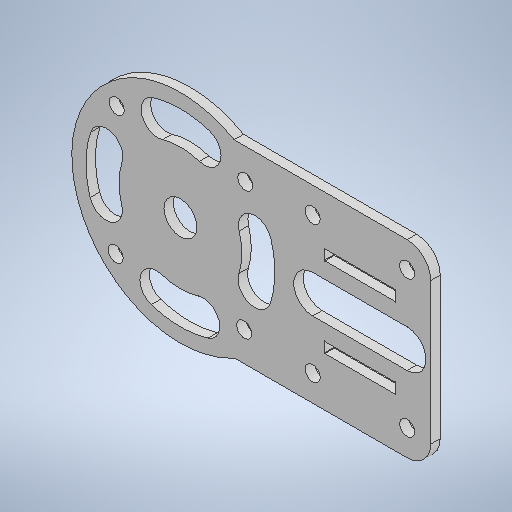
# Autodesk Inventor part: 3dp_pMount
Saved by Autodesk Inventor 2025.3 (Build 293356000, 356)
## iProperties
Created: 2026-10-04
Part Number: 3dp_pMount
Material: 一般
Document SubType Name: Modeling
Designer: yunto
Density: 1 g/cm^3
Appearance: 既定
Author: yunto
Autodesk Inventor part; units mm, degrees
ref_plane "YZ Plane" through (0, 0, 0) normal (1, 0, 0) x (0, 1, 0)
ref_plane "XZ Plane" through (0, 0, 0) normal (0, 1, 0) x (-1, 0, 0)
ref_plane "XY Plane" through (0, 0, 0) normal (0, 0, 1) x (1, 0, 0)
sketch "スケッチ1" plane through (0, 0, 0) normal (0, 0, 1) x (1, 0, 0)
  circle A0 centre (0, 0) radius 23
  circle A1 centre (0, 0) radius 3.5
  circle A2 centre (-13.4925, 13.7301) radius 1.6
  line L0 (-13.4925, 13.7301) -> (0, 0) construction
  circle A3 centre (-13.7301, -13.4925) radius 1.6
  circle A4 centre (13.4925, -13.7301) radius 1.6
  circle A5 centre (13.7301, 13.4925) radius 1.6
  line L1 (11.3578, 20) -> (53, 20)
  line L2 (53, 20) -> (53, -20)
  line L3 (53, -20) -> (11.3578, -20)
  line L4 (0, 23) -> (0, 0) construction
  line L5 (10.1768, -20.626) -> (11.4456, -20)
  arc A6 (-15.6924, 5.0988) -> (-15.779, -4.8241) centre (0, 0) ccw construction
  arc A7 (-19.0211, 6.1803) -> (-19.1261, -5.8474) centre (0, 0) ccw
  arc A8 (-12.3637, 4.0172) -> (-12.432, -3.8008) centre (0, 0) ccw
  arc A9 (-12.3637, 4.0172) -> (-19.0211, 6.1803) centre (-15.6924, 5.0988) ccw
  arc A10 (-19.1261, -5.8474) -> (-12.432, -3.8008) centre (-15.779, -4.8241) ccw
  arc A11 (-4.0172, -12.3637) -> (3.8008, -12.432) centre (0, 0) ccw
  arc A12 (-4.0172, -12.3637) -> (-6.1803, -19.0211) centre (-5.0988, -15.6924) ccw
  arc A13 (-6.1803, -19.0211) -> (5.8474, -19.1261) centre (0, 0) ccw
  arc A14 (5.8474, -19.1261) -> (3.8008, -12.432) centre (4.8241, -15.779) ccw
  arc A15 (12.3637, -4.0172) -> (12.432, 3.8008) centre (0, 0) ccw
  arc A16 (12.3637, -4.0172) -> (19.0211, -6.1803) centre (15.6924, -5.0988) ccw
  arc A17 (19.0211, -6.1803) -> (19.1261, 5.8474) centre (0, 0) ccw
  arc A18 (19.1261, 5.8474) -> (12.432, 3.8008) centre (15.779, 4.8241) ccw
  arc A19 (4.0172, 12.3637) -> (-3.8008, 12.432) centre (0, 0) ccw
  arc A20 (4.0172, 12.3637) -> (6.1803, 19.0211) centre (5.0988, 15.6924) ccw
  arc A21 (6.1803, 19.0211) -> (-5.8474, 19.1261) centre (0, 0) ccw
  arc A22 (-5.8474, 19.1261) -> (-3.8008, 12.432) centre (-4.8241, 15.779) ccw
  line L6 (-13.4925, 13.7301) -> (0, 0) construction
  line L7 (-16.4994, 0.144) -> (0, 0) construction
  line L8 (-15.779, -4.8241) -> (0, 0) construction
  line L9 (-15.6924, 5.0988) -> (0, 0) construction
  line L10 (48, -14.5) -> (28, -14.5) construction
  line L11 (28, -14.5) -> (28, 14.5) construction
  line L12 (28, 14.5) -> (48, 14.5) construction
  line L13 (48, 14.5) -> (48, -14.5) construction
  line L14 (48, -14.5) -> (28, 14.5) construction
  line L15 (28, -14.5) -> (48, 14.5) construction
  circle A23 centre (28, 14.5) radius 1.6
  circle A24 centre (48, 14.5) radius 1.6
  circle A25 centre (48, -14.5) radius 1.6
  circle A26 centre (28, -14.5) radius 1.6
  line L16 (0, 0) -> (38, 0) construction
  line L17 (45.5, -7.4) -> (30.5, -7.4)
  line L18 (30.5, -7.4) -> (30.5, -9.6)
  line L19 (30.5, -9.6) -> (45.5, -9.6)
  line L20 (45.5, -9.6) -> (45.5, -7.4)
  line L21 (45.5, -7.4) -> (30.5, -9.6) construction
  line L22 (30.5, -7.4) -> (45.5, -9.6) construction
  line L23 (38, 0) -> (38, -8.5) construction
  line L24 (45.5, 7.4) -> (30.5, 7.4)
  line L25 (30.5, 7.4) -> (30.5, 9.6)
  line L26 (30.5, 9.6) -> (45.5, 9.6)
  line L27 (45.5, 9.6) -> (45.5, 7.4)
  line L28 (45.5, 7.4) -> (30.5, 9.6) construction
  line L29 (30.5, 7.4) -> (45.5, 9.6) construction
  circle A27 centre (48, 0) radius 4
  circle A28 centre (28, 0) radius 4
  circle A29 centre (30.5, 9.6) radius 0.1
  circle A30 centre (30.5, 7.4) radius 0.1
  circle A31 centre (45.5, 9.6) radius 0.1
  circle A32 centre (45.5, 7.4) radius 0.1
  circle A33 centre (45.5, -7.4) radius 0.1
  circle A34 centre (30.5, -7.4) radius 0.1
  circle A35 centre (30.5, -9.6) radius 0.1
  circle A36 centre (45.5, -9.6) radius 0.1
  line L30 (28, 4) -> (48, 4)
  line L31 (48, -4) -> (28, -4)
  point P0 (38, 8.5)
  point P1 (45.4, -9.6)
  point P2 (30.6, -9.6)
  point P3 (30.5, -9.5)
  point P4 (30.5, -7.5)
  point P5 (30.6, -7.4)
  point P6 (45.4, -7.4)
  point P7 (45.5, -7.5)
  point P8 (45.5, -9.5)
  point P9 (45.4, 7.4)
  point P10 (30.6, 7.4)
  point P11 (30.5, 7.5)
  point P12 (30.5, 9.5)
  point P13 (30.6, 9.6)
  point P14 (45.4, 9.6)
  point P15 (45.5, 9.5)
  point P16 (45.5, 7.5)
  dimension "d0" = 7
  dimension "d1" = 46
  dimension "d2" = 19.25
  dimension "d3" = 3.2
  dimension "d6" = 360
  dimension "d19" = 44.5
  dimension "d31" = 360
  dimension "d33" = 45
  dimension "d35" = 13
  dimension "d36" = 20
  dimension "d37" = 35
  dimension "d38" = 3.2
  dimension "d39" = 20
  dimension "d40" = 5
  dimension "d41" = 29
  dimension "d42" = 38
  dimension "d43" = 40
  dimension "d44" = 2.2
  dimension "d45" = 15
  dimension "d46" = 8.5
  dimension "d47" = 8
  dimension "d48" = 0.2
  constraints: 64 end point, 43 point on circle, 37 centre point, 16 coincident, 11 equal radius, 8 point on line, 6 midpoint, 5 equal length, 5 symmetric about line, 5 tangent, 4 horizontal, 3 perpendicular, 3 vertical, 55 other
  measures "d0" diameter of A1
  measures "d1" diameter of A0
  measures "d2" distance of L0.start L0.end
  measures "d3" diameter of A2
  measures "d19" angle of L4 L0
  measures "d33" angle of L7 L0
  measures "d35" radius of A8
  measures "d36" radius of A7
  measures "d37" angle of L8 L9
  measures "d38" diameter of A23
  measures "d39" distance of L11.end L12.end
  measures "d40" distance between parallel lines of L2 L13
  measures "d41" distance of L12.end L10.start
  measures "d42" distance of point (38, 0) point (0, 0)
  measures "d43" distance of L1.end L2.end
  measures "d44" distance of L17.end L18.end
  measures "d45" distance of L17.start L17.end
  measures "d46" distance of L16.end L23.end
  measures "d47" diameter of A28
  measures "d48" diameter of A29
extrude "押し出し1" add sketch "スケッチ1" along normal blind 2
extrude "押し出し2" [suppressed]
fillet "フィレット1" radius 5 2 edges at (53, 20, 1) (53, -20, 1)
equation "\"pitchLength\" = 65"
equation "\"pRSdeg\" = 30deg"
equation "\"handDeg\" = 60deg"
